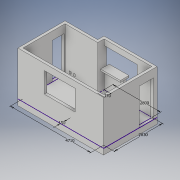
# Autodesk Inventor part: Sala
Saved by Autodesk Inventor 2019.3 (Build 233278000, 278)
## iProperties
Created: 2021-04-10
Part Number: Sala
Material: Generic
Document SubType Name: Modeling
Designer: mi001438
Density: 1 g/cm^3
Appearance: Default
Author: mi001438
Autodesk Inventor part; units mm, degrees
ref_plane "YZ Plane" through (0, 0, 0) normal (1, 0, 0) x (0, 1, 0)
ref_plane "XZ Plane" through (0, 0, 0) normal (0, 1, 0) x (-1, 0, 0)
ref_plane "XY Plane" through (0, 0, 0) normal (0, 0, 1) x (1, 0, 0)
sketch "Sketch1" plane through (0, 0, 0) normal (0, 1, 0) x (-1, 0, 0)
  line L0 (0, 0) -> (0, 2830)
  line L1 (0, 2830) -> (4710, 2830)
  line L2 (4710, 2830) -> (4710, 370)
  line L3 (4710, 370) -> (2800, 370)
  line L4 (2800, 370) -> (2800, 0)
  line L5 (2800, 0) -> (0, 0)
  line L6 (4860, 2980) -> (-150, 2980)
  line L7 (-150, 2980) -> (-150, -150)
  line L8 (-150, -150) -> (2950, -150)
  line L9 (2950, -150) -> (2950, 220)
  line L10 (2950, 220) -> (4860, 220)
  line L11 (4860, 220) -> (4860, 2980)
  dimension "d0" = 2830
  dimension "d2" = 370
  dimension "d3" = 2800
  dimension "d4" = 4710
  dimension "d5" = 150
  constraints: 24 end point, 10 perpendicular, 1 vertical, 5 other
  measures "d0" distance of L0.start L0.end
  measures "d2" distance between parallel lines of L3 L5
  measures "d3" distance of L4.end L0.start
  measures "d4" distance of L0.end L1.end
  measures "d5" distance between parallel lines of L1 L6
extrude "Extrusion1" add sketch "Sketch1" against normal blind 350 contours L0 L1 L2 L3 L4 L5 | L11 L10 L9 L8 L7 L6
extrude "Extrusion2" add sketch "Sketch1" along normal blind 2570 separate body
sketch "Sketch2" plane through (150, 0, 2980) normal (1, 0, 0) x (0, 0, -1)
  line L0 (2760, 0) -> (0, 0) projected
  line L1 (2090, 0) -> (2920, 0)
  line L2 (2920, 0) -> (2920, 2100)
  line L3 (2920, 2100) -> (2090, 2100)
  line L4 (2090, 2100) -> (2090, 0)
  line L5 (2980, 0) -> (2980, 2570) projected
  dimension "d10" = 830
  dimension "d11" = 2100
  dimension "d12" = 60
  constraints: 8 end point, 2 parallel, 1 horizontal, 1 perpendicular, 1 point on line
  measures "d10" distance of L2.end L3.end
  measures "d11" distance of L1.end L2.end
  measures "d12" distance between parallel lines of L5 L2
extrude "Extrusion3" cut sketch "Sketch2" against normal up to surface (150 mm away) bodies 2
sketch "Sketch3" plane through (-4710, 0, 370) normal (1, 0, 0) x (0, 0, -1)
  line L0 (-60, 0) -> (-760, 0)
  line L1 (-760, 0) -> (-760, 2100)
  line L2 (-760, 2100) -> (-60, 2100)
  line L3 (-60, 2100) -> (-60, 0)
  line L4 (0, 0) -> (-2460, 0) projected
  line L5 (0, 0) -> (0, 2570) projected
  point P0 (370, 0)
  dimension "d15" = 2100
  dimension "d16" = 700
  dimension "d17" = 60
  constraints: 8 end point, 2 parallel, 1 collinear, 1 horizontal, 1 perpendicular
  measures "d15" distance of L2.end L0.start
  measures "d16" distance of L1.end L2.end
  measures "d17" distance between parallel lines of L5 L3
extrude "Extrusion4" cut sketch "Sketch3" against normal up to surface (150 mm away) bodies 2
sketch "Sketch4" plane through (-4860, 0, 2980) normal (0, 0, 1) x (1, 0, 0)
  line L0 (1550, 2204) -> (3350, 2204)
  line L1 (3350, 2204) -> (3350, 1004)
  line L2 (3350, 1004) -> (1550, 1004)
  line L3 (1550, 1004) -> (1550, 2204)
  line L4 (0, 0) -> (5010, 0) projected
  line L5 (150, 0) -> (150, 2570) projected
  line L6 (4860, 0) -> (4860, 2570) projected
  dimension "d20" = 1200
  dimension "d21" = 1800
  dimension "d22" = 1004
  dimension "d23" = 1400
  dimension "d24" = 1510
  constraints: 8 end point, 2 parallel, 1 horizontal, 1 perpendicular
  measures "d20" distance of L2.end L0.start
  measures "d21" distance of L0.start L0.end
  measures "d22" distance between parallel lines of L4 L2
  measures "d23" distance between parallel lines of L3 L5
  measures "d24" distance between parallel lines of L6 L1
extrude "Extrusion5" cut sketch "Sketch4" against normal up to surface (150 mm away) bodies 2
sketch "Sketch5" plane through (150, 0, -150) normal (0, 0, -1) x (-1, 0, 0)
  line L0 (2950, 2245) -> (1010, 2245)
  line L1 (1010, 2245) -> (1010, 804.0348)
  line L2 (2950, 1045) -> (2950, 2245)
  line L3 (0, 0) -> (3100, 0) projected
  line L4 (1810, 1045) -> (1810, 0)
  line L5 (1810, 0) -> (1010, 0)
  line L6 (1010, 0) -> (1010, 804.0348)
  line L7 (1810, 1045) -> (2950, 1045)
  line L8 (150, 0) -> (150, 2570) projected
  dimension "d27" = 800
  dimension "d28" = 2245
  dimension "d29" = 1940
  dimension "d30" = 860
  dimension "d31" = 1045
  constraints: 14 end point, 3 parallel, 2 horizontal, 2 perpendicular, 1 point on line
  measures "d27" distance between parallel lines of L4 L6
  measures "d28" distance between parallel lines of L3 L0
  measures "d29" distance of L0.start L0.end
  measures "d30" distance between parallel lines of L8 L1
  measures "d31" distance between parallel lines of L7 L3
extrude "Extrusion6" cut sketch "Sketch5" against normal up to surface (150 mm away) bodies 2
sketch "Sketch6" plane through (-2800, 1045, -150) normal (0, 1, 0) x (1, 0, 0)
  line L0 (0, -350) -> (1160, -350)
  line L1 (1160, -350) -> (1160, 150)
  line L2 (1160, 150) -> (0, 150)
  line L3 (0, 150) -> (0, -350)
  line L4 (0, 0) -> (0, -150) projected
  line L5 (1140, -150) -> (0, -150) projected
  point P0 (2800, -150)
  dimension "d34" = 500
  dimension "d35" = 1160
  dimension "d36" = 200
  constraints: 8 end point, 2 parallel, 1 collinear, 1 horizontal, 1 perpendicular
  measures "d34" distance of L2.end L0.start
  measures "d35" distance of L0.start L0.end
  measures "d36" distance between parallel lines of L0 L5
extrude "Extrusion7" add sketch "Sketch6" along normal blind 100 separate body
sketch "Sketch7" plane through (-4710, 0, 370) normal (0, 0, 1) x (1, 0, 0)
  line L0 (350, 180) -> (250, 180)
  line L1 (250, 180) -> (250, 310)
  line L2 (250, 310) -> (350, 310)
  line L3 (350, 310) -> (350, 180)
  line L4 (300, 310) -> (300, 180)
  line L5 (0, 0) -> (0, 2570) projected
  line L6 (-150, 0) -> (4860, 0) projected
  line L7 (600, 180) -> (500, 180)
  line L8 (500, 180) -> (500, 310)
  line L9 (500, 310) -> (600, 310)
  line L10 (600, 310) -> (600, 180)
  line L11 (550, 310) -> (550, 180)
  point P0 (4710, 0)
  dimension "d39" = 300
  dimension "d40" = 100
  dimension "d41" = 130
  dimension "d42" = 180
  dimension "d43" = 100
  dimension "d44" = 130
  dimension "d45" = 150
  constraints: 20 end point, 4 midpoint, 4 parallel, 2 horizontal, 2 perpendicular, 1 collinear
  measures "d39" distance between parallel lines of L5 L4
  measures "d40" distance of L1.end L2.end
  measures "d41" distance of L2.end L0.start
  measures "d42" distance between parallel lines of L6 L0
  measures "d43" distance of L8.end L9.end
  measures "d44" distance of L9.end L7.start
  measures "d45" distance between parallel lines of L8 L3
extrude "Extrusion8" add sketch "Sketch7" along normal blind 5 separate body
sketch "Sketch8" plane through (0, 0, 2830) normal (0, 0, -1) x (-1, 0, 0)
  line L0 (250, 310) -> (350, 310)
  line L1 (350, 310) -> (350, 180)
  line L2 (350, 180) -> (250, 180)
  line L3 (250, 180) -> (250, 310)
  line L4 (500, 310) -> (600, 310)
  line L5 (600, 310) -> (600, 180)
  line L6 (600, 180) -> (500, 180)
  line L7 (500, 180) -> (500, 310)
  line L8 (4260, 310) -> (4360, 310)
  line L9 (4360, 310) -> (4360, 180)
  line L10 (4360, 180) -> (4260, 180)
  line L11 (4260, 180) -> (4260, 310)
  line L12 (300, 310) -> (300, 180)
  line L13 (550, 310) -> (550, 180)
  line L14 (-150, 0) -> (2950, 0) projected
  line L15 (0, 0) -> (0, 2570) projected
  line L16 (4310, 310) -> (4310, 180)
  line L17 (4710, 0) -> (4710, 2570) projected
  dimension "d48" = 100
  dimension "d49" = 130
  dimension "d50" = 100
  dimension "d51" = 180
  dimension "d52" = 300
  dimension "d53" = 150
  dimension "d54" = 130
  dimension "d55" = 100
  dimension "d56" = 400
  constraints: 30 end point, 6 midpoint, 6 parallel, 3 perpendicular, 2 horizontal, 2 point on line, 1 collinear
  measures "d48" distance of L0.start L0.end
  measures "d49" distance of L0.end L1.end
  measures "d50" distance of L4.start L4.end
  measures "d51" distance between parallel lines of L14 L2
  measures "d52" distance between parallel lines of L15 L12
  measures "d53" distance between parallel lines of L7 L1
  measures "d54" distance of L10.end L8.start
  measures "d55" distance of L8.start L8.end
  measures "d56" distance between parallel lines of L17 L16
extrude "Extrusion9" add sketch "Sketch8" along normal blind 5 separate body
body "Solid1"
body "Solid2"
body "Solid3"
body "Solid4"
body "Solid5"
